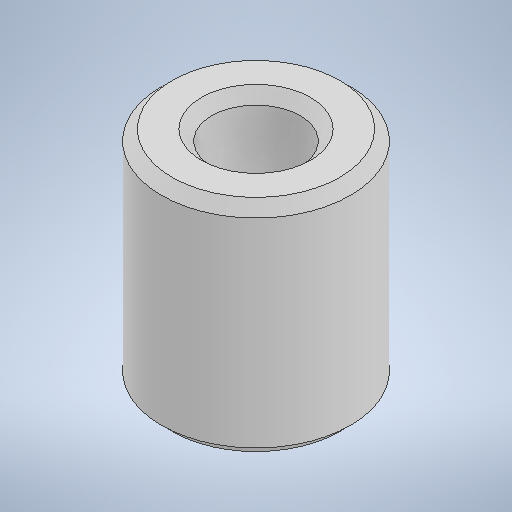
# Autodesk Inventor part: Arm pin
Saved by Autodesk Inventor 2025.3 (Build 293356000, 356)
## iProperties
Created: 2025-10-15
Part Number: Arm pin
Material: Generic
Document SubType Name: Modeling
Designer: kuuse
Density: 1 g/cm^3
Appearance: Default
Author: kuuse
## iProperties of the stored document Arm pin_3DPrint.ipt
Created: 2025-11-12
Part Number: Arm pin_3DPrint
Material: Generic
Document SubType Name: Modeling
Designer: kuuse
Density: 1 g/cm^3
Appearance: Default
Author: kuuse
Autodesk Inventor part; units mm, degrees
ref_plane "YZ Plane" through (0, 0, 0) normal (1, 0, 0) x (0, 1, 0)
ref_plane "XZ Plane" through (0, 0, 0) normal (0, 1, 0) x (-1, 0, 0)
ref_plane "XY Plane" through (0, 0, 0) normal (0, 0, 1) x (1, 0, 0)
sketch "Sketch1" plane through (0, 0, 0) normal (0, 0, 1) x (1, 0, 0)
  circle A0 centre (0, 0) radius 2.1
  circle A1 centre (0, 0) radius 4.5
  dimension "d0" = 4.2
  dimension "d1" = 9
  constraints: 2 centre point, 2 coincident
  measures "d0" diameter of A0
  measures "d1" diameter of A1
extrude "Extrusion1" add sketch "Sketch1" along normal blind 10.5
chamfer "Chamfer1" distance 0.5 angle 45 4 edges at (-2.1, 0, 10.5) (-4.5, 0, 10.5) (-4.5, 0, 0) (-2.1, 0, 0)
body "Solid1"
